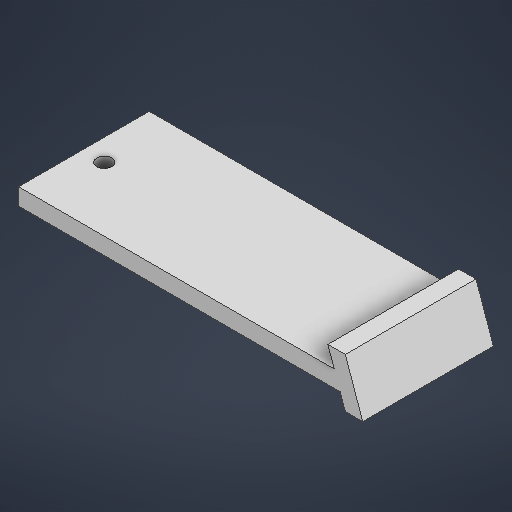
# Autodesk Inventor part: top
Saved by Autodesk Inventor 2026.1 (Build 301233020, 233B)
## iProperties
Created: 2026-04-17
Part Number: top
Material: Generic
Document SubType Name: Modeling
Designer: runek
Density: 1 g/cm^3
Appearance: Default
Author: runek
Autodesk Inventor part; units mm, degrees
ref_plane "YZ Plane" through (0, 0, 0) normal (1, 0, 0) x (0, 1, 0)
ref_plane "XZ Plane" through (0, 0, 0) normal (0, 1, 0) x (-1, 0, 0)
ref_plane "XY Plane" through (0, 0, 0) normal (0, 0, 1) x (1, 0, 0)
sketch "Sketch1" plane through (0, 0, 0) normal (0, 1, 0) x (-1, 0, 0)
  line L0 (0, 0) -> (0, 30)
  line L1 (0, 30) -> (75, 30)
  line L2 (75, 30) -> (75, 0)
  line L3 (75, 0) -> (0, 0)
  line L4 (0, 0) -> (4, 0)
  line L5 (4, 0) -> (4, 30)
  line L6 (75, 30) -> (65, 30)
  line L7 (65, 30) -> (65, 0)
  line L8 (75, 0) -> (65, 0)
  circle A0 centre (70, 15.307) radius 1.75
  dimension "d0" = 30
  dimension "d1" = 75
  dimension "d2" = 4
  dimension "d17" = 10
  dimension "d19" = 3.5
  constraints: 18 end point, 4 point on line, 3 perpendicular, 2 parallel, 1 centre point, 1 collinear, 1 vertical
  measures "d0" distance of L0.start L0.end
  measures "d1" distance of L0.end L1.end
  measures "d2" distance of L0.start L4.end
  measures "d17" distance of L1.end L6.end
  measures "d19" diameter of A0
extrude "Extrusion1" add sketch "Sketch1" along normal blind 3.84 contours L5 L1 L7 L3 | L7 L1 L2 L3
extrude "Extrusion2" add sketch "Sketch1" along normal blind 8 contours L0 L1 L5 L3
extrude "Extrusion3" add sketch "Sketch1" against normal blind 4.15 contours L0 L1 L5 L3
sketch "Sketch6" plane through (-75, 0, 30) normal (0, 0, 1) x (1, 0, 0)
  line L0 (71, 3.84) -> (71, 8) projected
  line L1 (71, 8) -> (75, -3.3523)
  line L2 (71, 8) -> (83.0364, 8) construction
  line L3 (75, -3.3523) -> (71, -3.3523)
  line L4 (71, -4.15) -> (75, -4.15) projected
  line L5 (71, -3.3523) -> (71, 0)
  line L6 (71, 0) -> (73.8188, 0)
  line L7 (0, 3.84) -> (71, 3.84) projected
  line L8 (71, 8) -> (71, 3.84)
  line L9 (71, 3.84) -> (72.4658, 3.84)
  line L10 (71, -3.3523) -> (75, -3.3523)
  line L11 (75, -3.3523) -> (75, -4.15)
  line L12 (75, -4.15) -> (71, -4.15)
  line L13 (71, -4.15) -> (71, -3.3523)
  point P0 (75, 0)
  dimension "d20" = 70.59
  constraints: 22 end point, 5 perpendicular, 3 parallel, 2 horizontal, 2 point on line, 1 equal length
  measures "d20" angle of L1 L2
extrude "Extrusion7" cut sketch "Sketch6" against normal blind 200
sketch "Sketch7" plane through (-75, 0, 30) normal (0, 0, 1) x (1, 0, 0)
  line L0 (75, -3.3523) -> (75, 8) projected
  line L1 (75, 8) -> (79, -3.3523)
  line L2 (75, 8) -> (87.0364, 8) construction
  line L3 (79, -3.3523) -> (75, -3.3523)
  line L4 (75, -3.3523) -> (75, 8)
  point P0 (75, 0)
  dimension "d23" = 70.59
  constraints: 8 end point, 2 perpendicular, 1 equal length, 1 horizontal
  measures "d23" angle of L1 L2
extrude "Extrusion8" add sketch "Sketch7" against normal blind 30
body "Solid1"
